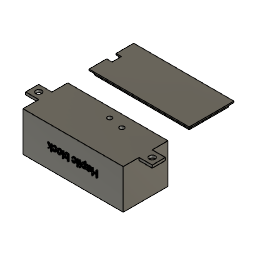
Haptic block - Case (Autodesk Fusion 360 design; units mm, degrees)
Autodesk Fusion 360 part; units mm, degrees
sketch "Sketch1" plane through (0, 0, 0) normal (0, 0, 1) x (1, 0, 0)
  line L0 (0, 0) -> (76, 0)
  line L1 (76, 0) -> (76, 34)
  line L2 (76, 34) -> (0, 34)
  line L3 (0, 34) -> (0, 0)
  dimension "d1" = 76
  dimension "d2" = 34
  constraint horizontal L0
  constraint vertical L1
  constraint horizontal L2
  constraint vertical L3
  constraint coincident L0.start L3.end
  measures "d1" distance of L0.start L0.end
  measures "d2" distance of L0.start L2.end
extrude "Extrude1" add sketch "Sketch1" along normal blind 26 makes body 1
shell "Shell1" thickness 2 removed faces 1 at (25.3333, 22.6667, 26) on bodies 1
sketch "Sketch2" plane through (0, 0, 0) normal (0, 0, -1) x (1, 0, 0)
  line L0 (0, 0) -> (0, -34)
  line L1 (0, -34) -> (76, -34)
  line L2 (76, -34) -> (76, 0)
  line L3 (76, 0) -> (0, 0)
  line L4 (0, -17) -> (76, -17)
  line L5 (38, 0) -> (38, -34)
  line L6 (76, -17) -> (58, -17)
  line L7 (58, -17) -> (58, 0)
  line L8 (58, -17) -> (58, -34)
  line L9 (58, -25) -> (50, -25)
  circle A0 centre (50, -25) radius 1.7
  line L10 (50, -25) -> (39, -25)
  line L11 (39, -25) -> (39, -26.8)
  circle A1 centre (39, -26.8) radius 1.7
  dimension "d7" = 18
  dimension "d8" = 8
  dimension "d9" = 3.4
  dimension "d10" = 11
  dimension "d11" = 1.8
  dimension "d12" = 3.4
  constraint midpoint L0 L4.start
  constraint midpoint L2 L4.end
  constraint midpoint L3 L5.start
  constraint midpoint L1 L5.end
  constraint perpendicular L2 L6
  constraint coincident L3 L7.end
  constraint perpendicular L3 L7
  constraint coincident L1 L8.end
  constraint perpendicular L1 L8
  constraint coincident L8 L9.start
  constraint perpendicular L8 L9
  constraint coincident L9.end A0.centre
  constraint parallel L9 L10
  constraint perpendicular L10 L11
  constraint coincident L11.end A1.centre
  measures "d7" distance of L4.end L6.end
  measures "d8" distance of L9.start L9.end
  measures "d9" diameter of A0
  measures "d10" distance of L9.end L10.end
  measures "d11" distance of L10.end L11.end
  measures "d12" diameter of A1
extrude "Extrude2" cut sketch "Sketch2" against normal blind 100 contours L5 A1 | L5 A1 | L9 A0 L10 | L9 A0 L10 bodies 1
sketch "Sketch3" plane through (0, 0, 2) normal (0, 0, 1) x (-1, 0, 0)
  circle A0 centre (-39, -26.8) radius 1.7
  circle A1 centre (-50, -25) radius 1.7
  line L0 (-2, -32) -> (-2, -2)
  line L1 (-2, -2) -> (-74, -2)
  line L2 (-74, -2) -> (-74, -32)
  line L3 (-74, -32) -> (-2, -32)
  circle A2 centre (-39, -26.8) radius 3.5
  circle A3 centre (-50, -25) radius 3.5
  dimension "d15" = 7
  dimension "d16" = 7
  constraint concentric A0 A2
  constraint concentric A1 A3
  measures "d15" diameter of A2
  measures "d16" diameter of A3
extrude "Extrude3" add sketch "Sketch3" along normal blind 5.2 contours A2 | A3 bodies 1
extrude "Extrude4" add 2 faces at (36.1194, 27.0583, 7.2) (47.1194, 25.2583, 7.2) along direction (0, 0, -1) blind 12.4 on bodies 1 bodies 1
extrude "Extrude5" cut 2 faces at (36.1194, 27.0583, 7.2) (47.1194, 25.2583, 7.2) along direction (0, 0, -1) blind 5.2 on bodies 1 bodies 1
extrude "Extrude6" add 1 faces at (26, 0.6667, 26) along direction (0, 0, -1) blind 56 on bodies 1 bodies 1
extrude "Extrude7" cut 1 faces at (26, 0.6667, 26) along direction (0, 0, -1) blind 26 on bodies 1 bodies 1
extrude "Extrude8" add 1 faces at (13.2822, 19.7605, 0) along direction (0, 0, -1) blind 2 on bodies 1 bodies 1
extrude "Extrude9" add 2 faces at (47.1194, 25.2583, -5.2) (36.1194, 27.0583, -5.2) along direction (0, 0, -1) blind 2 on bodies 1 bodies 1
extrude "Extrude10" cut 1 faces at (41.8739, 9.1142, 2) along direction (0, 0, -1) blind 2 on bodies 1 bodies 1
sketch "Sketch4" plane through (0, 0, 0) normal (-1, 0, 0) x (0, -1, 0)
  line L0 (0, 0) -> (-34, 0)
  line L1 (-34, 0) -> (-34, -30)
  line L2 (-34, -30) -> (0, -30)
  line L3 (0, -30) -> (0, 0)
  line L4 (-34, 0) -> (-17, 0)
  line L5 (-17, 0) -> (-22, 0)
  line L6 (-22, 0) -> (-12, 0)
  line L7 (-12, 0) -> (-12, -2)
  line L8 (-12, -2) -> (-22, -2)
  line L9 (-22, -2) -> (-22, 0)
  dimension "d33" = 17
  dimension "d34" = 5
  dimension "d35" = 10
  dimension "d36" = 2
  constraint coincident L0.end L1.start
  constraint perpendicular L1 L4
  constraint perpendicular L3 L5
  constraint horizontal L6
  constraint vertical L7
  constraint horizontal L8
  constraint vertical L9
  measures "d33" distance of L0.end L4.end
  measures "d34" distance of L4.end L5.end
  measures "d35" distance of L5.end L6.end
  measures "d36" distance of L5.end L8.end
extrude "Extrude11" add sketch "Sketch4" along normal blind 10 contours L0 L4 L5 L6 L7 L8 L9 bodies 1
extrude "Extrude12" add 1 faces at (-10, 18.6667, -1.3333) along direction (1, 0, 0) blind 96 on bodies 1 bodies 1
sketch "Sketch5" plane through (0, 0, -2) normal (0, 0, -1) x (1, 0, 0)
  line L0 (76, -12) -> (76, -22)
  line L1 (76, -22) -> (86, -22)
  line L2 (86, -22) -> (86, -12)
  line L3 (86, -12) -> (76, -12)
  circle A0 centre (81, -17) radius 2.25
  circle A1 centre (-5, -17) radius 2.25
  dimension "d41" = 4.5
  dimension "d42" = 4.5
  measures "d41" diameter of A0
  measures "d42" diameter of A1
extrude "Extrude13" cut sketch "Sketch5" against normal blind 243891 contours A0 | A1 bodies 1
sketch "Sketch6" plane through (0, 0, 0) normal (0, 0, 1) x (1, 0, 0)
  line L0 (0, 50) -> (76, 50)
  line L1 (76, 50) -> (76, 84)
  line L2 (76, 84) -> (0, 84)
  line L3 (0, 84) -> (0, 50)
  dimension "d45" = 76
  dimension "d46" = 34
  constraint horizontal L0
  constraint vertical L1
  constraint horizontal L2
  constraint vertical L3
  measures "d45" distance of L0.start L0.end
  measures "d46" distance of L0.start L2.end
extrude "Extrude14" add sketch "Sketch6" along normal blind 1 separate body makes body 2
sketch "Sketch7" plane through (0, 0, 0) normal (0, 0, -1) x (1, 0, 0)
  line L0 (0, -50) -> (0, -84)
  line L1 (0, -84) -> (76, -84)
  line L2 (76, -84) -> (76, -50)
  line L3 (76, -50) -> (0, -50)
  line L4 (73.9, -52.1) -> (2.1, -52.1)
  line L5 (2.1, -52.1) -> (2.1, -81.9)
  line L6 (2.1, -81.9) -> (73.9, -81.9)
  line L7 (73.9, -81.9) -> (73.9, -52.1)
  line L8 (73.9, -52.1) -> (2.1, -81.9) construction
  line L9 (2.1, -52.1) -> (73.9, -81.9) construction
  point P0 (38, -67)
  dimension "d49" = 71.8
  dimension "d50" = 29.8
  constraint horizontal L4
  constraint perpendicular L4 L5
  constraint parallel L4 L6
  constraint parallel L5 L7
  constraint coincident L8 P0
  constraint coincident L9 P0
  measures "d49" distance of L5.end L6.end
  measures "d50" distance of L4.end L5.end
extrude "Extrude15" add sketch "Sketch7" along normal blind 3 contours L4 L5 L6 L7 bodies 2
shell "Shell2" thickness 1 removed faces 1 at (26.0333, 62.0333, -3) on bodies 2
extrude "Extrude16" add 1 faces at (26.3667, 62.3667, 0) along direction (0, 0, -1) blind 0.5 on bodies 2 bodies 2
sketch "Sketch8" plane through (0, 0, -0.5) normal (0, 0, -1) x (1, 0, 0)
  line L0 (72.9, -80.9) -> (72.9, -53.1)
  line L1 (72.9, -53.1) -> (3.1, -53.1)
  line L2 (3.1, -53.1) -> (3.1, -80.9)
  line L3 (3.1, -80.9) -> (72.9, -80.9)
  line L4 (0, -67) -> (3.1, -67)
  line L5 (3.1, -67) -> (3.1, -63.5)
  line L6 (3.1, -63.5) -> (0, -63.5)
  line L7 (0, -63.5) -> (0, -67)
  line L8 (0, -67) -> (3.1, -67)
  line L9 (3.1, -67) -> (3.1, -70.5)
  line L10 (3.1, -70.5) -> (0, -70.5)
  line L11 (0, -70.5) -> (0, -67)
  dimension "d56" = 3.5
  dimension "d57" = 3.1
  dimension "d58" = 3.5
  constraint horizontal L4
  constraint vertical L5
  constraint horizontal L6
  constraint vertical L7
  constraint horizontal L8
  constraint vertical L9
  constraint horizontal L10
  constraint vertical L11
  measures "d56" distance of L4.start L6.end
  measures "d57" distance of L4.start L4.end
  measures "d58" distance of L4.start L10.end
extrude "Extrude17" cut sketch "Sketch8" against normal blind 6 contours L2 L4 L8 L9 L10 L11 | L2 L4 L5 L6 L7 L8 bodies 2
extrude "Extrude18" cut 1 faces at (2.7667, 68.1667, -0.5) along direction (0, 0, -1) blind 34 on bodies 2 bodies 2
sketch "Sketch9" plane through (0, 0, 0) normal (0, -1, 0) x (1, 0, 0)
  line L0 (76, 0) -> (0, 0)
  line L1 (0, 0) -> (0, -30)
  line L2 (0, -30) -> (76, -30)
  line L3 (76, -30) -> (76, 0)
  line L4 (76, 1) -> (0, 1) construction
  line L5 (0, 1) -> (0, -30) construction
  line L6 (0, -30) -> (76, -30) construction
  line L7 (76, -30) -> (76, 1) construction
  dimension "d63" = 5
  text T0 "Haptic block" font "Arial" height 5 align centre middle in box 76 x 31 at (76, 1) x (-1, 0) y (0, -1) spacing 1 kerned
  constraint coincident L2.end
extrude "Extrude19" add sketch "Sketch9" along normal blind 0.7 text T0 bodies 1
extrude "Extrude20" cut 1 faces at (3.1, 65.8333, 0) along direction (1, 0, 0) blind 1 on bodies 2 bodies 2
equation "d19 = -5.2 mm - 2 mm - 5.2 mm"
equation "d23 = -26 mm - 30 mm"
equation "d33 = ( 34 / 2 ) * 1 mm"
equation "d39 = -10 mm - 10 mm - 76 mm"
equation "d50 = 34 mm - ( 76 mm - 71.8 mm )"
equation "d64 = 'Haptic block'"
